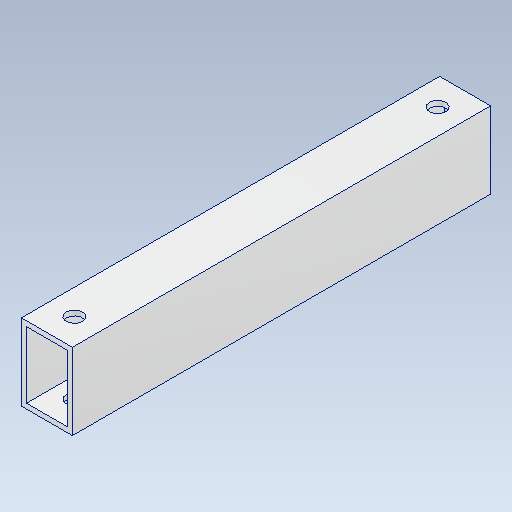
# Autodesk Inventor part: alsp_10_15_82_1
Saved by Autodesk Inventor 2027.1 (Build 311270010, 270A)
## iProperties
Created: 2026-10-29
Part Number: alsp_10_15_82_1
Material: アルミニウム 6061
Document SubType Name: Modeling
Designer: ug_nd
Density: 2.7 g/cm^3
Appearance: アルミニウム - フラット
Author: ug_nd
Autodesk Inventor part; units mm, degrees
ref_plane "YZ Plane" through (0, 0, 0) normal (1, 0, 0) x (0, 1, 0)
ref_plane "XZ Plane" through (0, 0, 0) normal (0, 1, 0) x (-1, 0, 0)
ref_plane "XY Plane" through (0, 0, 0) normal (0, 0, 1) x (1, 0, 0)
sketch "スケッチ1" plane through (0, 0, 0) normal (0, 0, 1) x (1, 0, 0)
  line L0 (-5, -7.5) -> (5, -7.5)
  line L1 (5, -7.5) -> (5, 7.5)
  line L2 (5, 7.5) -> (-5, 7.5)
  line L3 (-5, 7.5) -> (-5, -7.5)
  line L4 (-5, -7.5) -> (5, 7.5) construction
  line L5 (5, -7.5) -> (-5, 7.5) construction
  line L6 (-4, -6.5) -> (4, -6.5)
  line L7 (4, -6.5) -> (4, 6.5)
  line L8 (4, 6.5) -> (-4, 6.5)
  line L9 (-4, 6.5) -> (-4, -6.5)
  line L10 (-4, -6.5) -> (4, 6.5) construction
  line L11 (4, -6.5) -> (-4, 6.5) construction
  point P0 (0, 0)
  dimension "d0" = 10
  dimension "d1" = 15
  dimension "d2" = 1
  dimension "d3" = 1
  constraints: 24 end point, 4 midpoint, 4 parallel, 2 horizontal, 2 perpendicular
  measures "d0" distance of L1.end L2.end
  measures "d1" distance of L2.end L0.start
  measures "d2" distance between parallel lines of L8 L2
  measures "d3" distance between parallel lines of L3 L9
extrude "押し出し1" add sketch "スケッチ1" along normal mid plane 82
sketch "スケッチ2" plane through (-5, 7.5, 41) normal (0, 1, 0) x (1, 0, 0)
  line L0 (-99.3079, 41) -> (460.6921, 41) construction
  line L1 (5, 321) -> (5, -239) construction
  circle A0 centre (180.6921, 41) radius 200 construction
  line L2 (180.6921, 41) -> (80.6921, 214.2051) construction
  line L3 (180.6921, 41) -> (80.6921, -132.2051) construction
  line L4 (80.6921, 214.2051) -> (34.282, 41) construction
  line L5 (80.6921, -132.2051) -> (34.282, 41) construction
  line L6 (44.4699, 223.9108) -> (3.7059, 71.7775)
  line L7 (116.9143, 204.4994) -> (76.1503, 52.366)
  line L8 (44.4699, 223.9108) -> (116.9143, 204.4994)
  circle A1 centre (5, 76.6071) radius 1.6
  circle A2 centre (5, 5.3929) radius 1.6
  point P0 (5, 41)
  dimension "d6" = 400
  dimension "d7" = 120
  dimension "d9" = 150
  dimension "d10" = 75
  dimension "d11" = 157.5
  dimension "d12" = 5
  dimension "d13" = 3.2
  constraints: 14 end point, 4 symmetric about line, 3 point on line, 2 centre point, 2 midpoint, 1 coincident, 1 parallel, 4 other
  measures "d7" angle of L3 L2
  measures "d9" angle of L5 L4
  measures "d10" distance between parallel lines of L7 L6
  measures "d11" distance of L6.start L6.end
  measures "d12" distance of L6.end point (5, 76.607)
  measures "d13" diameter of A1
extrude "押し出し2" cut sketch "スケッチ2" against normal through all
